DSCaseIlOWERcORNER v2 (Autodesk Fusion 360 design; units mm, degrees)
Autodesk Fusion 360 part; units mm, degrees
sketch "Sketch1" plane through (0, 0, 0) normal (0, 0, 1) x (1, 0, 0)
  line L0 (13.5, -13.5) -> (-13.5, -13.5)
  line L1 (-13.5, -13.5) -> (-13.5, 13.5)
  line L2 (-13.5, 13.5) -> (13.5, 13.5)
  line L3 (13.5, 13.5) -> (13.5, -13.5)
  line L4 (13.5, -13.5) -> (-13.5, 13.5) construction
  line L5 (-13.5, -13.5) -> (13.5, 13.5) construction
  dimension "d1" = 27
  dimension "d2" = 27
  constraint perpendicular L0 L1
  constraint parallel L0 L2
  constraint parallel L1 L3
  constraint horizontal L0
  constraint coincident L4 origin
  constraint coincident L5 origin
  measures "d1" distance of L1.end L2.end
  measures "d2" distance of L0.end L1.end
extrude "Extrude1" add sketch "Sketch1" along normal blind 2 makes body 1
sketch "Sketch2" plane through (0, 0, 2) normal (0, 0, 1) x (1, 0, 0)
  line L0 (13.5, 13.5) -> (-13.5, 13.5)
  line L1 (-13.5, 13.5) -> (-13.5, -13.5)
  line L2 (-13.5, -13.5) -> (13.5, -13.5)
  line L3 (13.5, -13.5) -> (13.5, 13.5)
  line L4 (13.5, -13.5) -> (-11.5, -13.5)
  line L5 (-11.5, -13.5) -> (-11.5, 11.5)
  line L6 (-11.5, 11.5) -> (13.5, 11.5)
  line L7 (13.5, 11.5) -> (13.5, -13.5)
  dimension "d5" = 25
  dimension "d6" = 25
  constraint horizontal L4
  constraint vertical L5
  constraint horizontal L6
  constraint vertical L7
  constraint coincident L2.end L3.start
  measures "d5" distance of L2.end L6.end
  measures "d6" distance of L2.end L4.end
extrude "Extrude2" add sketch "Sketch2" along normal blind 16 contours L0 L1 L2 L3 L5 L6 bodies 1
sketch "Sketch3" plane through (0, 0, 18) normal (0, 0, 1) x (1, 0, 0)
  line L0 (-11.5, 11.5) -> (13.5, 11.5)
  line L1 (13.5, 11.5) -> (13.5, 13.5)
  line L2 (13.5, 13.5) -> (-13.5, 13.5)
  line L3 (-13.5, 13.5) -> (-13.5, -13.5)
  line L4 (-13.5, -13.5) -> (-11.5, -13.5)
  line L5 (-11.5, -13.5) -> (-11.5, 11.5)
  line L6 (-13.5, 13.5) -> (13.5, 13.5)
  line L7 (13.5, 13.5) -> (13.5, -13.5)
  line L8 (13.5, -13.5) -> (-13.5, -13.5)
  line L9 (-13.5, -13.5) -> (-13.5, 13.5)
  point P0 (13.5, -13.5)
  constraint horizontal L6
  constraint vertical L7
  constraint horizontal L8
  constraint vertical L9
  constraint coincident P0 L7.end
  constraint coincident L2.end L3.start
extrude "Extrude3" add sketch "Sketch3" along normal blind 2 bodies 1
sketch "Sketch5" plane through (13.5, 0, 0) normal (1, 0, 0) x (0, 0, -1)
  line L0 (0, -13.5) -> (0, 13.5)
  line L1 (0, 13.5) -> (-20, 13.5)
  line L2 (-20, 13.5) -> (-20, -13.5)
  line L3 (-20, -13.5) -> (-18, -13.5)
  line L4 (-18, -13.5) -> (-18, 11.5)
  line L5 (-18, 11.5) -> (-2, 11.5)
  line L6 (-2, 11.5) -> (-2, -13.5)
  line L7 (-2, -13.5) -> (0, -13.5)
  line L8 (-10.5, 13.5) -> (-9.5, 13.5)
  line L9 (-8.954, 12) -> (-11.046, 12)
  line L10 (-11.046, 12) -> (-10.5, 13.5)
  line L11 (-9.5, 13.5) -> (-8.954, 12)
extrude "Extrude5" cut sketch "Sketch5" against normal blind 25 contours L1 L8 L9 L10 L11 bodies 1
sketch "Sketch6" plane through (0, -13.5, 0) normal (0, -1, 0) x (1, 0, 0)
  line L0 (-13.5, 0) -> (13.5, 0)
  line L1 (13.5, 0) -> (13.5, 2)
  line L2 (13.5, 2) -> (-11.5, 2)
  line L3 (-11.5, 2) -> (-11.5, 18)
  line L4 (-11.5, 18) -> (13.5, 18)
  line L5 (13.5, 18) -> (13.5, 20)
  line L6 (13.5, 20) -> (-13.5, 20)
  line L7 (-13.5, 20) -> (-13.5, 0)
  line L8 (0, 0) -> (0.5, 0)
  line L9 (1.625, 1.5) -> (0.5, 0)
  line L10 (0.5, 0) -> (-0.5, 0)
  line L11 (-0.5, 0) -> (-1.625, 1.5)
  line L12 (-1.625, 1.5) -> (1.625, 1.5)
  constraint coincident L8.start origin
  constraint horizontal L8
extrude "Extrude6" cut sketch "Sketch6" against normal blind 10 contours L0 L8 L9 L10 L11 L12 bodies 1
sketch "Sketch7" plane through (0, 11.5, 0) normal (0, -1, 0) x (1, 0, 0)
  line L0 (-11.5, 2) -> (13.5, 2)
  line L1 (13.5, 2) -> (13.5, 18)
  line L2 (13.5, 18) -> (-11.5, 18)
  line L3 (-11.5, 18) -> (-11.5, 2)
  line L4 (13.5, 18) -> (11.5, 18)
  line L5 (11.5, 18) -> (11.5, 2)
  line L6 (11.5, 2) -> (13.5, 2)
  line L7 (13.5, 2) -> (13.5, 18)
  dimension "d39" = 16
  dimension "d40" = 2
  constraint horizontal L4
  constraint vertical L5
  constraint horizontal L6
  constraint vertical L7
  constraint coincident L1.end L2.start
  measures "d39" distance of L1.end L0.end
  measures "d40" distance of L1.end L4.end
extrude "Extrude7" add sketch "Sketch7" along normal blind 25 contours L0 L1 L2 L4 L5 L6 L7 bodies 1
sketch "Sketch8" plane through (0, -13.5, 0) normal (0, -1, 0) x (1, 0, 0)
  line L0 (11.5, 2) -> (-11.5, 2)
  line L1 (-11.5, 2) -> (-11.5, 18)
  line L2 (-11.5, 18) -> (11.5, 18)
  line L3 (11.5, 18) -> (11.5, 2)
  line L4 (13.5, 0) -> (13.5, 20)
  line L5 (13.5, 20) -> (-13.5, 20)
  line L6 (-13.5, 20) -> (-13.5, 0)
  line L7 (-13.5, 0) -> (-0.5, 0)
  line L8 (-0.5, 0) -> (-1.625, 1.5)
  line L9 (-1.625, 1.5) -> (1.625, 1.5)
  line L10 (1.625, 1.5) -> (0.5, 0)
  line L11 (0.5, 0) -> (13.5, 0)
  line L12 (-11.5, 2) -> (-13.5, 2)
  line L13 (-11.5, 18) -> (-13.5, 18)
  constraint coincident L0.end L1.start
  constraint coincident L6 L12.end
  constraint perpendicular L6 L12
  constraint coincident L1.end L2.start
  constraint coincident L6 L13.end
  constraint perpendicular L6 L13
extrude "Extrude8" cut sketch "Sketch8" against normal blind 25 contours L1 L6 L12 L13 bodies 1
mirror "Mirror1" about plane through (0, 0, 0) normal (0, 0, 1) of bodies 1 makes body 2
move_body "Move1" bodies 2 to x (1, 0, 0) y (0, 1, 0) z (0, 0, 1) at (0, 0, -5)
sketch "Sketch9" plane through (0, -13.5, 0) normal (0, -1, 0) x (1, 0, 0)
  line L0 (-13.5, -7) -> (11.5, -7)
  line L1 (11.5, -7) -> (11.5, -23)
  line L2 (11.5, -23) -> (-13.5, -23)
  line L3 (-13.5, -23) -> (-13.5, -25)
  line L4 (-13.5, -25) -> (13.5, -25)
  line L5 (13.5, -25) -> (13.5, -5)
  line L6 (13.5, -5) -> (0.5, -5)
  line L7 (0.5, -5) -> (1.625, -6.5)
  line L8 (1.625, -6.5) -> (-1.625, -6.5)
  line L9 (-1.625, -6.5) -> (-0.5, -5)
  line L10 (-0.5, -5) -> (-13.5, -5)
  line L11 (-13.5, -5) -> (-13.5, -7)
  line L12 (0.5, -5) -> (-0.5, -5)
  line L13 (0, -5) -> (0, -3)
  line L14 (0, -3) -> (2, -3)
  line L15 (0, -3) -> (-2, -3)
  line L16 (-0.5, -5) -> (-2, -3)
  line L17 (0.5, -5) -> (2, -3)
  line L18 (0, -3) -> (0, -3.5)
  line L19 (0, -3.5) -> (1.625, -3.5)
  line L20 (0, -3.5) -> (-1.625, -3.5)
  dimension "d46" = 2
  dimension "d47" = 2
  dimension "d48" = 2
  dimension "d51" = 0.5
  constraint midpoint L12 L13.start
  constraint vertical L13
  constraint horizontal L15
  constraint coincident L9.end L10.start
  constraint coincident L6.end L7.start
  constraint vertical L18
  constraint coincident L17 L19.end
  constraint perpendicular L13 L19
  constraint coincident L16 L20.end
  constraint perpendicular L13 L20
  measures "d46" distance of L13.start L13.end
  measures "d47" distance of L13.end L14.end
  measures "d48" distance of L13.end L15.end
  measures "d51" distance of L13.end L18.end
extrude "Extrude9" add sketch "Sketch9" against normal blind 10 contours L7 L8 L9 L12 | L12 L13 L16 L20 | L12 L13 L17 L19 bodies 2
sketch "Sketch10" plane through (-2.72, 0, -2.04) normal (-0.8, 0, -0.6) x (-0.6, 0, 0.8)
  line L0 (-3.7, -13.5) -> (-1.825, -13.5)
  line L1 (-1.825, -13.5) -> (-1.825, -3.5)
  line L2 (-1.825, -3.5) -> (-3.7, -3.5)
  line L3 (-3.7, -3.5) -> (-3.7, -13.5)
extrude "Extrude10" cut sketch "Sketch10" against normal blind 0.1 bodies 2
sketch "Sketch11" plane through (2.72, 0, -2.04) normal (0.8, 0, -0.6) x (-0.6, 0, -0.8)
  line L0 (1.825, -13.5) -> (3.7, -13.5)
  line L1 (3.7, -13.5) -> (3.7, -3.5)
  line L2 (3.7, -3.5) -> (1.825, -3.5)
  line L3 (1.825, -3.5) -> (1.825, -13.5)
extrude "Extrude11" cut sketch "Sketch11" against normal blind 0.1 bodies 2
move_face "OffsetFaces1" offset -0.1 1 faces at (0.5, -6.8333, -3.5) on bodies 2
